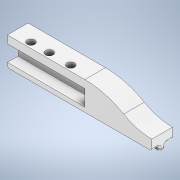
# Autodesk Inventor part: P2_V4_001
Saved by Autodesk Inventor 2020 (Build 240168000, 168)
## iProperties
Created: 2022-06-02
Part Number: P2_V4_001
Material: Water
Document SubType Name: Modeling
Designer: drago
Density: 0.9983 g/cm^3
Appearance: Snow
Author: drago
Autodesk Inventor part; units mm, degrees
ref_plane "YZ Plane" through (0, 0, 0) normal (1, 0, 0) x (0, 1, 0)
ref_plane "XZ Plane" through (0, 0, 0) normal (0, 1, 0) x (-1, 0, 0)
ref_plane "XY Plane" through (0, 0, 0) normal (0, 0, 1) x (1, 0, 0)
sketch "Sketch1" plane through (0, 0, 0) normal (0, 0, 1) x (1, 0, 0)
  line L0 (0, 45) -> (-280, 45)
  line L1 (-280, 45) -> (-280, 100)
  line L2 (-280, 100) -> (0, 100)
  line L3 (0, 100) -> (0, 45)
  point P0 (0, 0)
  dimension "d0" = 280
  dimension "d47" = 0
  dimension "d48" = 55
  constraints: 8 end point, 2 parallel, 1 horizontal, 1 perpendicular, 1 other
  measures "d0" distance of L1.end L2.end
  measures "d47" distance from line of point (0, 0) L3
  measures "d48" distance of L0.end L1.end
extrude "Extrusion1" add sketch "Sketch1" along normal blind 40
sketch "Sketch2" plane through (0, 0, 40) normal (0, 0, 1) x (1, 0, 0)
  line L0 (0, 100) -> (0, 100)
  line L1 (-280, 100) -> (-280, 45) projected
  line L2 (0, 45) -> (0, 100) projected
  line L3 (0, 100) -> (-280, 100) projected
  line L4 (-280, 100) -> (-280, 45) projected
  line L5 (-280, 45) -> (0, 45) projected
  line L6 (-280, 54) -> (-130, 54)
  line L7 (-280, 85) -> (-280, 54)
  line L8 (-130, 85) -> (-130, 54.0297)
  line L9 (-130, 54) -> (-130, 54.0297)
  line L10 (-280, 85) -> (-130, 85)
  line L11 (0, 45) -> (0, 100) projected
  point P0 (-180, 55)
  dimension "d233" = 150
  dimension "d253" = 0
  constraints: 12 end point, 2 horizontal, 2 vertical, 1 collinear, 1 point on line, 1 other
  measures "d233" distance of L7.start L8.start
  measures "d253" distance between parallel lines of L1 L7
sketch "Sketch3" plane through (0, 0, 40) normal (0, 0, 1) x (1, 0, 0)
  line L0 (0, 100) -> (-280, 100) projected
  line L1 (-280, 100) -> (-280, 45) projected
  line L2 (-280, 45) -> (0, 45) projected
  line L3 (0, 45) -> (0, 100) projected
  line L4 (0, 45) -> (0, 100) projected
  line L5 (0, 100) -> (-130, 100)
  line L6 (0, 100) -> (-280, 100) projected
  arc A0 (-280, 65) -> (-225.3103, 79.7241) centre (-280, 173.9286) ccw
  line L7 (-280, 100) -> (-280, 45) projected
  line L8 (-130, 100) -> (-280, 100)
  line L9 (-280, 45) -> (-280, 100)
  line L10 (-280, 45) -> (0, 45) construction
  line L11 (0, 65) -> (0, 45)
  arc A1 (-54.6897, 79.7241) -> (0, 65) centre (0, 173.9286) ccw
  arc A2 (-54.6897, 79.7241) -> (-130, 100) centre (-130, -50) ccw
  line L12 (0, 65) -> (0, 45)
  line L13 (0, 45) -> (0, 65)
  point P0 (-200, 100)
  point P1 (-280, 65)
  point P2 (0, 100)
  point P3 (-130, 100)
  dimension "d203" = 20
  dimension "d256" = 150
  dimension "d257" = 108.9286
  dimension "d258" = 108.9286
  dimension "d259" = 0
  dimension "d260" = 20
  dimension "d271" = 150
  constraints: 12 end point, 7 point on circle, 4 point on line, 3 centre point, 2 collinear, 2 line through centre
  measures "d203" distance of L1.end A0.start
  measures "d256" radius of A2
  measures "d257" radius of A0
  measures "d258" radius of A1
  measures "d259" distance between parallel lines of L3 L11
  measures "d260" distance of L11.end L11.start
  measures "d271" distance of L0.end L5.end
extrude "Extrusion3" cut sketch "Sketch3" against normal up to next contours L3 A1 A2 L0
extrude "Extrusion6" cut sketch "Sketch2" against normal blind 21 contours L10 L8 L9 L6 L1
sketch "Sketch10" plane through (0, 45, 0) normal (1, 0, 0) x (0, 0, -1)
  line L0 (0, 0) -> (-40, 0) projected
  line L1 (0, 0) -> (-14.25, 0)
  line L2 (-40, 0) -> (-25.75, 0)
  line L3 (0, 0) -> (-40, 0) projected
  line L4 (-14.25, 0) -> (-14.25, -10)
  line L5 (-14.25, -10) -> (-25.75, -10)
  line L6 (-25.75, -10) -> (-25.75, 0)
  point P0 (0, -45)
  point P1 (-14.25, 0)
  point P2 (-25.75, 0)
  dimension "d95" = 11.5
  dimension "d96" = 10
  constraints: 10 end point, 2 perpendicular, 2 point on line, 1 collinear, 1 vertical
  measures "d95" distance of L4.end L5.end
  measures "d96" distance of L5.end L2.end
extrude "Extrusion10" add sketch "Sketch10" against normal up to surface (280 mm away)
fillet "Fillet3" radius 4 4 edges at (-140, 45, 14.25) (-140, 45, 25.75) (-140, 35, 25.75) (-140, 35, 14.25)
fillet "Fillet4" radius 4 18 edges at (0, 40, 25.75) (0, 43.8284, 26.9216) (0, 45, 34.875) (0, 35, 20) (0, 36.1716, 15.4216) (0, 40, 14.25) (0, 43.8284, 13.0784) (0, 45, 5.125) (0, 36.1716, 24.5784) (-280, 43.8284, 26.9216) (-280, 40, 25.75) (-280, 36.1716, 24.5784) (-280, 35, 20) (-280, 36.1716, 15.4216) (-280, 40, 14.25) (-280, 43.8284, 13.0784) (-280, 45, 5.125) (-280, 45, 34.875)
sketch "Sketch24" plane through (0, 0, 0) normal (0, 0, -1) x (-1, 0, 0)
  line L0 (280, 100) -> (280, 49) projected
  line L1 (0, 49) -> (0, 65) projected
  arc A0 (0, 49) -> (4, 45) centre (4, 49) ccw projected
  line L2 (276, 45) -> (4, 45) projected
  arc A1 (276, 45) -> (280, 49) centre (276, 49) ccw projected
  line L3 (280, 100) -> (280, 49) projected
  line L4 (130, 100) -> (280, 100) projected
  line L5 (5, 49) -> (5, 59)
  arc A2 (130, 100) -> (54.6897, 79.7241) centre (130, -50) ccw projected
  arc A3 (0, 65) -> (54.6897, 79.7241) centre (0, 173.9286) ccw projected
  line L6 (275, 49) -> (275, 95)
  arc A4 (5, 59) -> (98.7841, 80.2932) centre (5, 276.1781) ccw
  line L7 (275, 95) -> (163.5586, 95)
  arc A5 (163.5586, 95) -> (98.7841, 80.2932) centre (163.5586, -55) ccw
  line L8 (275, 49) -> (5, 49)
  point P0 (0, 0)
  point P1 (280, 65)
  dimension "d215" = 10
  dimension "d261" = 5
  dimension "d262" = 5
  constraints: 8 end point, 4 point on circle, 2 centre point, 1 horizontal, 1 perpendicular, 1 vertical
  measures "d215" distance of L5.start L5.end
  measures "d261" distance between parallel lines of L1 L5
  measures "d262" distance between parallel lines of L0 L6
extrude "Extrusion19" cut sketch "Sketch24" against normal blind 12 contours L5 A4 A5 L7 L6 L8
fillet "Fillet19" radius 2 1 edges at (-5, 54, 12)
sketch "Sketch25" plane through (0, 100, 40) normal (0, 1, 0) x (1, 0, 0)
  line L0 (-130, 0) -> (-280, 0) projected
  line L1 (-130, 40) -> (-280, 40) projected
  line L2 (-150, 10.5) -> (0, 10.5) construction
  line L3 (0, 10.25) -> (0, 18.25) construction
  circle A0 centre (-245, 10.5) radius 7.5
  circle A1 centre (-209.5, 10.5) radius 7.5
  circle A2 centre (-168, 10.5) radius 7.5
  line L4 (0, 40) -> (-280, 40) construction
  line L5 (-276, 0) -> (-4, 0) construction
  line L6 (-15, 40) -> (-15, 0) construction
  line L7 (-245, 10.5) -> (-245, -7.5107)
  line L8 (-245, -7.5107) -> (-209.5, -7.5107)
  line L9 (-209.5, -7.5107) -> (-209.5, 10.5)
  line L10 (-209.5, -7.5107) -> (-168, -7.5107)
  line L11 (-280, 40) -> (-280, 0) projected
  line L12 (-130, 40) -> (-130, 0) projected
  line L13 (-163.5586, 40) -> (-275, 40) construction
  line L14 (-265, 40) -> (-265, 0) construction
  line L15 (-130, 0) -> (-280, 0) construction
  line L16 (-163.5586, 40) -> (-98.7841, 40) construction
  line L17 (-145, 40) -> (-145, 0) construction
  line L18 (-168, -7.5107) -> (-168, 10.5) construction
  line L19 (-130, 0) -> (-130, 21) construction
  line L20 (-163.5586, 28) -> (-98.7841, 28) construction
  point P0 (0, 40)
  dimension "d219" = 15
  dimension "d220" = 15
  dimension "d221" = 15
  dimension "d222" = 10.5
  dimension "d265" = 15
  dimension "d267" = 20
  dimension "d268" = 23
  dimension "d272" = 15
  dimension "d273" = 41.5
  constraints: 18 end point, 11 point on line, 4 perpendicular, 3 centre point, 2 vertical, 1 parallel
  measures "d219" diameter of A0
  measures "d220" diameter of A1
  measures "d221" diameter of A2
  measures "d222" distance between parallel lines of L0 L2
  measures "d265" distance between parallel lines of L11 L14
  measures "d267" distance between parallel lines of L14 L7
  measures "d268" distance between parallel lines of L17 L18
  measures "d272" distance from line of L19.end L17
  measures "d273" distance of L8.end L10.end
extrude "Extrusion20" cut sketch "Sketch25" against normal up to surface (15 mm away) contours A0 | A1 | A2
body "Solid1"
